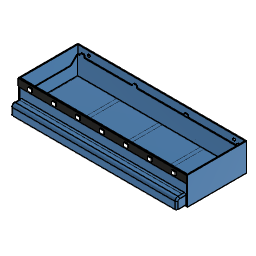
Large_Drawer_Assembly (Autodesk Fusion 360 design; units mm, degrees)
Autodesk Fusion 360 part; units mm, degrees
sketch "Bottom" plane through (0, 0, 0) normal (0, 0, 1) x (1, 0, 0) in component "Large_Holder_PRINT v2"
  line L0 (0, 0) -> (232.6, 0)
  line L1 (232.6, 0) -> (232.6, 81.6)
  line L2 (232.6, 81.6) -> (0, 81.6)
  line L3 (0, 81.6) -> (0, 0)
  line L4 (1.2, 80.4) -> (231.4, 80.4)
  line L5 (231.4, 80.4) -> (231.4, 1.2)
  line L6 (231.4, 1.2) -> (1.2, 1.2)
  line L7 (1.2, 1.2) -> (1.2, 80.4)
  line L8 (3.2, 3.2) -> (3.2, 78.4)
  line L9 (33.4, 80.4) -> (34.2, 80.4)
  line L10 (34.2, 1.2) -> (33.4, 1.2)
  line L11 (66.4, 80.4) -> (67.2, 80.4)
  line L12 (67.2, 1.2) -> (66.4, 1.2)
  line L13 (99.4, 80.4) -> (100.2, 80.4)
  line L14 (100.2, 1.2032) -> (99.4, 1.2032)
  line L15 (132.4, 80.4) -> (133.2, 80.4)
  line L16 (133.2, 1.2) -> (132.4, 1.2)
  line L17 (165.4, 80.4) -> (166.2, 80.4)
  line L18 (166.2, 1.2) -> (165.4, 1.2)
  line L19 (198.4, 80.4) -> (199.2, 80.4)
  line L20 (199.2, 1.2) -> (198.4, 1.2)
  line L21 (229.4, 78.4) -> (229.4, 3.2)
  line L22 (231.4, 80.4) -> (232.2, 80.4)
  line L23 (232.2, 1.2) -> (231.4, 1.2)
  line L24 (3.2, 78.4) -> (113.9, 78.4)
  line L25 (113.9, 3.2) -> (3.2, 3.2)
  line L26 (229.4, 78.4) -> (118.7, 78.4)
  line L27 (229.4, 3.2) -> (113.8, 3.2)
  line L28 (118.7, 78.4) -> (113.9, 78.4)
  line L29 (113.9, 3.2) -> (113.8, 3.2)
  line L30 (56, 80.4) -> (56, 1.2)
  line L31 (61, 80.4) -> (61, 1.2)
  line L32 (113.8, 80.4) -> (113.8, 1.2)
  line L33 (118.8, 1.2) -> (118.8, 80.4)
  line L34 (171.6, 3.2) -> (171.6, 80.4)
  line L35 (176.6, 80.4) -> (176.6, 1.2)
  line L36 (171.6, 3.2) -> (171.6, 1.2)
  dimension "d1_1" = 1.2
  dimension "d2_1" = 1.2
  dimension "d3_1" = 1.2
  dimension "d4_1" = 1.2
  dimension "d5_1" = 2
  dimension "d8_1" = 81.6
  dimension "d52" = 2
  dimension "d191" = 2
  dimension "d192" = 2
  dimension "d194" = 2
  dimension "d195" = 2
  dimension "d306" = 5
  dimension "d307" = 5
  dimension "d308" = 52.8
  dimension "d311" = 52.8
  dimension "d312" = 52.8
  dimension "d313" = 5
  dimension "d318" = 52.8
  constraint horizontal L0
  constraint vertical L1
  constraint horizontal L2
  constraint vertical L3
  constraint coincident L0.start L3.end
  constraint horizontal L4
  constraint vertical L5
  constraint horizontal L6
  constraint vertical L7
  constraint vertical L8
  constraint horizontal L9
  constraint coincident L6 L10.start
  constraint coincident L4 L9.start
  constraint horizontal L11
  constraint horizontal L12
  constraint coincident L4 L11.start
  constraint horizontal L13
  constraint horizontal L14
  constraint coincident L4 L13.start
  constraint horizontal L15
  constraint horizontal L16
  constraint coincident L4 L15.start
  constraint horizontal L17
  constraint horizontal L18
  constraint coincident L4 L17.start
  constraint horizontal L19
  constraint horizontal L20
  constraint coincident L4 L19.start
  constraint vertical L21
  constraint horizontal L22
  constraint horizontal L23
  constraint coincident L4 L5.start
  constraint perpendicular L8 L25
  constraint coincident L4 L30.start
  constraint coincident L6 L30.end
  constraint perpendicular L6 L30
  constraint coincident L4 L31.start
  constraint coincident L6 L31.end
  constraint perpendicular L0 L31
  constraint coincident L4 L32.start
  constraint coincident L6 L32.end
  constraint perpendicular L6 L32
  constraint coincident L6 L33.start
  constraint perpendicular L4 L33
  constraint coincident L4 L33.end
  constraint midpoint L27 L34.start
  constraint coincident L4 L34.end
  constraint perpendicular L4 L34
  constraint coincident L4 L35.start
  constraint coincident L6 L35.end
  constraint perpendicular L6 L35
  constraint coincident L6 L36.end
  constraint perpendicular L6 L36
  measures "d1_1" distance of L3 L7
  measures "d2_1" distance of L2 L4
  measures "d3_1" distance of L0 L6
  measures "d4_1" distance of L1 L5
  measures "d5_1" distance of L7 L8
  measures "d8_1" distance of L0.start L2.end
  measures "d52" distance of L5 L21
  measures "d191" distance of L4 L24
  measures "d192" distance of L6 L25
  measures "d194" distance of L6 L27
  measures "d195" distance of L4 L26
  measures "d306" distance of L30 L31
  measures "d307" distance of L32 L33
  measures "d308" distance of L8 L30
  measures "d311" distance of L31 L32
  measures "d312" distance of L33 L34
  measures "d313" distance of L34 L35
  measures "d318" distance of L21 L35
extrude "Extrude2" add sketch "Bottom" along normal blind 38.2 makes body 1 in component "Large_Holder_PRINT v2"
sketch "Front" plane through (0, 0, 0) normal (0, -1, 0) x (1, 0, 0) in component "Large_Holder_PRINT v2"
  line L0 (0, 0) -> (232.6, 0)
  line L1 (232.6, 0) -> (232.6, 38.2)
  line L2 (232.6, 38.2) -> (0, 38.2)
  line L3 (0, 38.2) -> (0, 0)
  line L4 (1.2, 28.2) -> (33.4, 28.2)
  line L5 (33.4, 1.2) -> (1.2, 1.2)
  line L6 (1.2, 1.2) -> (1.2, 28.2)
  line L7 (1.2, 0) -> (1.2, 38.2)
  line L8 (231.4, 28.2) -> (231.4, 1.2)
  line L9 (33.4, 28.2) -> (231.4, 28.2)
  line L10 (231.4, 1.2) -> (33.4, 1.2)
  dimension "d80" = 27
  dimension "d83" = 10
  dimension "d91" = 27
  dimension "d319" = 1.2
  constraint horizontal L4
  constraint horizontal L5
  constraint vertical L6
  constraint collinear L6 L7
  constraint vertical L8
  constraint perpendicular L8 L9
  measures "d80" distance of L4.start L5.end
  measures "d83" distance of L2 L4
  measures "d91" distance of L8.start L8.end
  measures "d319" distance of L1 L8
sketch "Back" plane through (0, 80.4, 0) normal (0, -1, 0) x (1, 0, 0) in component "Large_Holder_PRINT v2"
  line L0 (231.4, 0) -> (231.4, 38.2)
  line L1 (231.4, 38.2) -> (1.2, 38.2)
  line L2 (1.2, 38.2) -> (1.2, 0)
  line L3 (3.2, 6.7355) -> (6.7355, 3.2)
  line L4 (6.7355, 3.2) -> (27.8645, 3.2)
  line L5 (6.7355, 26.2711) -> (3.2, 22.7355)
  line L6 (3.2, 22.7355) -> (3.2, 6.7355)
  line L7 (27.8645, 26.271) -> (27.8645, 26.2711)
  line L8 (31.4, 6.7355) -> (31.4, 22.7355)
  line L9 (31.4, 22.7355) -> (27.8645, 26.2711)
  line L10 (1.2, 0) -> (231.4, 0)
  line L11 (27.8645, 3.2) -> (31.4, 6.7355)
  line L12 (27.8645, 26.271) -> (6.7355, 26.2711)
  line L13 (60.8645, 26.2728) -> (39.7355, 26.2729)
  line L14 (39.7355, 26.2729) -> (36.2, 22.7374)
  line L15 (36.2, 22.7374) -> (36.2, 6.7374)
  line L16 (36.2, 6.7374) -> (39.7355, 3.2019)
  line L17 (39.7355, 3.2019) -> (60.8645, 3.2019)
  line L18 (60.8645, 3.2019) -> (64.4, 6.7374)
  line L19 (64.4, 6.7374) -> (64.4, 22.7374)
  line L20 (93.8645, 26.271) -> (72.7355, 26.2711)
  line L21 (72.7355, 26.2711) -> (69.2, 22.7355)
  line L22 (69.2, 22.7355) -> (69.2, 6.7355)
  line L23 (69.2, 6.7355) -> (72.7355, 3.2)
  line L24 (72.7355, 3.2) -> (93.8645, 3.2)
  line L25 (93.8645, 3.2) -> (97.4, 6.7355)
  line L26 (97.4, 6.7355) -> (97.4, 22.7355)
  line L27 (126.8645, 26.271) -> (105.7355, 26.2711)
  line L28 (105.7355, 26.2711) -> (102.2, 22.7355)
  line L29 (102.2, 22.7355) -> (102.2, 6.7355)
  line L30 (102.2, 6.7355) -> (105.7355, 3.2)
  line L31 (105.7355, 3.2) -> (126.8645, 3.2)
  line L32 (126.8645, 3.2) -> (130.4, 6.7355)
  line L33 (130.4, 6.7355) -> (130.4, 22.7355)
  line L34 (159.8645, 26.271) -> (138.7355, 26.2711)
  line L35 (138.7355, 26.2711) -> (135.2, 22.7355)
  line L36 (135.2, 22.7355) -> (135.2, 6.7355)
  line L37 (135.2, 6.7355) -> (138.7355, 3.2)
  line L38 (138.7355, 3.2) -> (159.8645, 3.2)
  line L39 (159.8645, 3.2) -> (163.4, 6.7355)
  line L40 (163.4, 6.7355) -> (163.4, 22.7355)
  line L41 (192.8645, 26.271) -> (171.7355, 26.2711)
  line L42 (171.7355, 26.2711) -> (168.2, 22.7355)
  line L43 (168.2, 22.7355) -> (168.2, 6.7355)
  line L44 (168.2, 6.7355) -> (171.7355, 3.2)
  line L45 (171.7355, 3.2) -> (192.8645, 3.2)
  line L46 (192.8645, 3.2) -> (196.4, 6.7355)
  line L47 (196.4, 6.7355) -> (196.4, 22.7355)
  line L48 (225.8645, 26.271) -> (204.7355, 26.2711)
  line L49 (204.7355, 26.2711) -> (201.2, 22.7355)
  line L50 (201.2, 22.7355) -> (201.2, 6.7355)
  line L51 (201.2, 6.7355) -> (204.7355, 3.2)
  line L52 (204.7355, 3.2) -> (225.8645, 3.2)
  line L53 (225.8645, 3.2) -> (229.4, 6.7355)
  line L54 (229.4, 6.7355) -> (229.4, 22.7355)
  line L55 (232.6, 0) -> (232.6, 38.2)
  line L56 (0, 0) -> (0, 38.2)
  line L57 (60.8645, 26.2728) -> (64.4, 22.7374)
  line L58 (97.4, 22.7355) -> (93.8645, 26.271)
  line L59 (130.4, 22.7355) -> (126.8645, 26.271)
  line L60 (163.4, 22.7355) -> (159.8645, 26.271)
  line L61 (196.4, 22.7355) -> (192.8645, 26.271)
  line L62 (229.4, 22.7355) -> (225.8645, 26.271)
  dimension "d97" = 5
  dimension "d99" = 5
  dimension "d179" = 5
  dimension "d201" = 28.2
  dimension "d202" = 5
  dimension "d206" = 3.2
  dimension "d208" = 135
  dimension "d209" = 135
  dimension "d210" = 135
  dimension "d212" = 16
  dimension "d213" = 21.1289
  dimension "d215" = 135
  dimension "d216" = 135
  dimension "d219" = 5
  dimension "d220" = 5
  dimension "d222" = 28.2
  dimension "d223" = 5
  dimension "d224" = 16
  dimension "d225" = 135
  dimension "d226" = 135
  dimension "d228" = 16
  dimension "d229" = 21.1289
  dimension "d230" = 135
  dimension "d232" = 5
  dimension "d233" = 5
  dimension "d235" = 28.2
  dimension "d236" = 5
  dimension "d238" = 135
  dimension "d239" = 135
  dimension "d241" = 16
  dimension "d242" = 21.1289
  dimension "d243" = 135
  dimension "d245" = 5
  dimension "d246" = 5
  dimension "d248" = 28.2
  dimension "d249" = 5
  dimension "d250" = 16
  dimension "d251" = 135
  dimension "d252" = 135
  dimension "d254" = 16
  dimension "d255" = 21.1289
  dimension "d256" = 135
  dimension "d258" = 5
  dimension "d259" = 5
  dimension "d261" = 28.2
  dimension "d262" = 5
  dimension "d263" = 16
  dimension "d264" = 135
  dimension "d265" = 135
  dimension "d267" = 16
  dimension "d268" = 21.1289
  dimension "d269" = 135
  dimension "d271" = 5
  dimension "d272" = 5
  dimension "d274" = 28.2
  dimension "d275" = 5
  dimension "d276" = 16
  dimension "d277" = 135
  dimension "d278" = 135
  dimension "d280" = 16
  dimension "d281" = 21.1289
  dimension "d282" = 135
  dimension "d284" = 5
  dimension "d285" = 5
  dimension "d287" = 28.2
  dimension "d288" = 5
  dimension "d289" = 16
  dimension "d290" = 135
  dimension "d291" = 135
  dimension "d293" = 16
  dimension "d294" = 21.1289
  dimension "d295" = 135
  dimension "d297" = 4.8
  dimension "d298" = 4.8
  dimension "d299" = 4.8
  dimension "d300" = 4.8
  dimension "d301" = 4.8
  dimension "d302" = 4.8
  dimension "d304" = 3.2
  dimension "d305" = 4.9999
  dimension "d320" = 3.2019
  dimension "d321" = 3.2
  dimension "d323" = 3.2
  constraint parallel L2 L6
  constraint vertical L8
  constraint vertical L19
  constraint vertical L26
  constraint vertical L33
  constraint vertical L40
  constraint vertical L47
  constraint vertical L54
  measures "d97" distance of L5.start L5.end
  measures "d99" distance of L3.start L3.end
  measures "d179" distance of L8.end L7.end
  measures "d201" distance of L6 L8
  measures "d202" distance of L4.end L8.start
  measures "d206" distance of L4 L10
  measures "d208" angle of L3 L4
  measures "d209" angle of L8 L11
  measures "d210" angle of L8 L9
  measures "d212" distance of L3.start L5.end
  measures "d213" horizontal distance of L7.start L5.start
  measures "d215" angle of L5 L12
  measures "d216" angle of L9 L12
  measures "d219" distance of L14.end L13.end
  measures "d220" distance of L15.end L16.end
  measures "d222" distance of L15 L19
  measures "d223" distance of L18.end L17.end
  measures "d224" distance of L18.end L19.end
  measures "d225" angle of L16 L17
  measures "d226" angle of L18 L19
  measures "d228" distance of L15.end L14.end
  measures "d229" horizontal distance of L13.start L13.end
  measures "d230" angle of L13 L14
  measures "d232" distance of L21.end L20.end
  measures "d233" distance of L22.end L23.end
  measures "d235" distance of L22 L26
  measures "d236" distance of L25.end L24.end
  measures "d238" angle of L23 L24
  measures "d239" angle of L25 L26
  measures "d241" distance of L22.end L21.end
  measures "d242" horizontal distance of L20.start L20.end
  measures "d243" angle of L20 L21
  measures "d245" distance of L28.end L27.end
  measures "d246" distance of L29.end L30.end
  measures "d248" distance of L29 L33
  measures "d249" distance of L32.end L31.end
  measures "d250" distance of L32.end L33.end
  measures "d251" angle of L30 L31
  measures "d252" angle of L32 L33
  measures "d254" distance of L29.end L28.end
  measures "d255" horizontal distance of L27.start L27.end
  measures "d256" angle of L27 L28
  measures "d258" distance of L35.end L34.end
  measures "d259" distance of L36.end L37.end
  measures "d261" distance of L36 L40
  measures "d262" distance of L39.end L38.end
  measures "d263" distance of L39.end L40.end
  measures "d264" angle of L37 L38
  measures "d265" angle of L39 L40
  measures "d267" distance of L36.end L35.end
  measures "d268" horizontal distance of L34.start L34.end
  measures "d269" angle of L34 L35
  measures "d271" distance of L42.end L41.end
  measures "d272" distance of L43.end L44.end
  measures "d274" distance of L43 L47
  measures "d275" distance of L46.end L45.end
  measures "d276" distance of L46.end L47.end
  measures "d277" angle of L44 L45
  measures "d278" angle of L46 L47
  measures "d280" distance of L43.end L42.end
  measures "d281" horizontal distance of L41.start L41.end
  measures "d282" angle of L41 L42
  measures "d284" distance of L49.end L48.end
  measures "d285" distance of L50.end L51.end
  measures "d287" distance of L50 L54
  measures "d288" distance of L53.end L52.end
  measures "d289" distance of L53.end L54.end
  measures "d290" angle of L51 L52
  measures "d291" angle of L53 L54
  measures "d293" distance of L50.end L49.end
  measures "d294" horizontal distance of L48.start L48.end
  measures "d295" angle of L48 L49
  measures "d297" distance of L8 L15
  measures "d298" distance of L19 L22
  measures "d299" distance of L26 L29
  measures "d300" distance of L33 L36
  measures "d301" distance of L40 L43
  measures "d302" distance of L47 L50
  measures "d304" distance of L6 L56
  measures "d305" distance of L40.end L34.start
  measures "d320" distance of L10 L17
  measures "d321" distance of L10 L24
  measures "d323" distance of L10 L31
sketch "Mounting" plane through (0, 80.4, 0) normal (0, -1, 0) x (1, 0, 0) in component "Large_Holder_PRINT v2"
  line L0 (231.4, 0) -> (231.4, 38.2)
  line L1 (231.4, 38.2) -> (1.2, 38.2)
  line L2 (1.2, 38.2) -> (1.2, 0)
  circle A0 centre (216.3, 32.2) radius 2
  circle A1 centre (16.3, 32.2) radius 2
  line L3 (1.2, 0) -> (231.4, 0)
  dimension "d165" = 4
  dimension "d166" = 4
  dimension "d167" = 15.1
  dimension "d168" = 6
  dimension "d169" = 15.1
  dimension "d170" = 6
  measures "d165" diameter of A0
  measures "d166" diameter of A1
  measures "d167" distance of L2 A1.centre
  measures "d168" distance of L1 A1.centre
  measures "d169" distance of L0 A0.centre
  measures "d170" distance of L1 A0.centre
extrude "Extrude9" cut sketch "Front" against normal up to surface (1.2 mm away) contours L4 L5 L6 L7 L8 L9 L10 bodies 1 in component "Large_Holder_PRINT v2"
extrude "Extrude10" cut sketch "Back" against normal blind 1.2 contours L3 L4 L5 L6 L8 L9 L11 L12 | L13 L14 L15 L16 L17 L18 L19 L57 | L20 L21 L22 L23 L24 L25 L26 L58 | L27 L28 L29 L30 L31 L32 L33 L59 | L34 L35 L36 L37 L38 L39 L40 L60 | L41 L42 L43 L44 L45 L46 L47 L61 | L48 L49 L50 L51 L52 L53 L54 L62 bodies 1 in component "Large_Holder_PRINT v2"
extrude "Extrude11" cut sketch "Mounting" against normal blind 1.2 contours A0 | A1 bodies 1 in component "Large_Holder_PRINT v2"
extrude "Extrude12" add sketch "Bottom" along normal up to surface (1.2 mm away) contours L4 L6 L7 L8 L9 L10 L24 L25 L30 | L4 L24 L30 L31 | L4 L11 L13 L24 L31 L32 | L6 L25 L30 L31 | L6 L12 L25 L31 L32 | L4 L24 L26 L28 L32 L33 | L6 L25 L27 L29 L32 L33 | L4 L15 L17 L26 L33 L34 | L6 L16 L18 L27 L33 L36 | L4 L26 L34 L35 | L6 L27 L35 L36 | L4 L5 L6 L19 L20 L21 L26 L27 L35 bodies 1 in component "Large_Holder_PRINT v2"
extrude "Extrude13" add sketch "Bottom" along normal up to surface (1.2 mm away) contours L4 L6 L7 L8 L9 L10 L24 L25 L30 | L4 L24 L30 L31 | L4 L11 L13 L24 L31 L32 | L6 L25 L30 L31 | L6 L12 L25 L31 L32 | L4 L24 L26 L28 L32 L33 | L6 L25 L27 L29 L32 L33 | L4 L15 L17 L26 L33 L34 | L6 L16 L18 L27 L33 L36 | L4 L26 L34 L35 | L6 L27 L35 L36 | L4 L5 L6 L19 L20 L21 L26 L27 L35 bodies 1 in component "Large_Holder_PRINT v2"
extrude "Extrude15" add sketch "Bottom" along normal blind 1.2 contours L24 L25 L30 L31 | L24 L25 L26 L27 L28 L29 L32 L33 | L26 L27 L34 L35 bodies 1 in component "Large_Holder_PRINT v2"
sketch "Sketch1" plane through (0, 0, 0) normal (0, 0, 1) x (1, 0, 0) in component "Large_Drawer_PRINT v1"
  line L0 (0, 0) -> (229.4, 0)
  line L1 (229.4, 0) -> (229.4, 80)
  line L2 (229.4, 80) -> (0, 80)
  line L3 (0, 80) -> (0, 0)
  dimension "d1_2" = 229.4
  dimension "d2_2" = 80
  constraint horizontal L0
  constraint vertical L1
  constraint horizontal L2
  constraint vertical L3
  constraint coincident L0.start L3.end
  measures "d1_2" distance of L0.start L0.end
  measures "d2_2" distance of L0.end L1.end
extrude "Extrude1" add sketch "Sketch1" along normal blind 26.2 separate body makes body 2 in component "Large_Drawer_PRINT v1"
shell "Shell1" thickness 0.8 removed faces 1 at (76.4667, 26.6667, 26.2) on bodies 2 in component "Large_Drawer_PRINT v1"
ref_plane "WorkPlane1" through (211, 40, 13.1) normal (1, 0, 0) x (0, 1, 0) in component "Large_Drawer_PRINT v1"
sketch "Sketch3" plane through (0, 80, 0) normal (0, 1, 0) x (-1, 0, 0) in component "Large_Drawer_PRINT v1"
  line L0 (-229.4, 0) -> (0, 0)
  line L1 (0, 0) -> (0, 26.2)
  line L2 (0, 26.2) -> (-229.4, 26.2)
  line L3 (-229.4, 26.2) -> (-229.4, 0)
  line L4 (-114.7, 26.2) -> (-114.7, 0) construction
  line L5 (-225.15, 27.45) -> (-225.15, 28.45)
  line L6 (-223.9, 29.7) -> (-220.9, 29.7)
  line L7 (-219.65, 28.45) -> (-219.65, 27.45)
  line L8 (-226.4, 26.2) -> (-218.4, 26.2)
  arc A0 (-226.4, 26.2) -> (-225.15, 27.45) centre (-226.4, 27.45) ccw
  arc A1 (-223.9, 29.7) -> (-225.15, 28.45) centre (-223.9, 28.45) ccw
  arc A2 (-219.65, 28.45) -> (-220.9, 29.7) centre (-220.9, 28.45) ccw
  arc A3 (-219.65, 27.45) -> (-218.4, 26.2) centre (-218.4, 27.45) ccw
  arc A4 (-4.25, 28.45) -> (-5.5, 29.7) centre (-5.5, 28.45) ccw
  line L9 (-5.5, 29.7) -> (-8.5, 29.7)
  arc A5 (-11, 26.2) -> (-9.75, 27.45) centre (-11, 27.45) ccw
  arc A6 (-4.25, 27.45) -> (-3, 26.2) centre (-3, 27.45) ccw
  line L10 (-4.25, 27.45) -> (-4.25, 28.45)
  line L11 (-3, 26.2) -> (-11, 26.2)
  arc A7 (-8.5, 29.7) -> (-9.75, 28.45) centre (-8.5, 28.45) ccw
  line L12 (-9.75, 28.45) -> (-9.75, 27.45)
  line L13 (-151.4, 29.7129) -> (-148.4, 29.7129)
  arc A8 (-151.4, 29.7129) -> (-152.65, 28.4629) centre (-151.4, 28.4629) ccw
  line L14 (-152.65, 27.4629) -> (-152.65, 28.4629)
  arc A9 (-153.9, 26.2129) -> (-152.65, 27.4629) centre (-153.9, 27.4629) ccw
  arc A10 (-147.15, 27.4629) -> (-145.9, 26.2129) centre (-145.9, 27.4629) ccw
  line L15 (-153.9, 26.2129) -> (-145.9, 26.2129)
  line L16 (-147.15, 28.4629) -> (-147.15, 27.4629)
  arc A11 (-147.15, 28.4629) -> (-148.4, 29.7129) centre (-148.4, 28.4629) ccw
  line L17 (-81, 29.7) -> (-78, 29.7)
  arc A12 (-81, 29.7) -> (-82.25, 28.45) centre (-81, 28.45) ccw
  line L18 (-82.25, 27.45) -> (-82.25, 28.45)
  arc A13 (-83.5, 26.2) -> (-82.25, 27.45) centre (-83.5, 27.45) ccw
  arc A14 (-76.75, 28.45) -> (-78, 29.7) centre (-78, 28.45) ccw
  line L19 (-76.75, 28.45) -> (-76.75, 27.45)
  arc A15 (-76.75, 27.45) -> (-75.5, 26.2) centre (-75.5, 27.45) ccw
  point P0 (-222.4, 29.7)
  point P1 (-7, 29.7)
  dimension "d18_1" = 7
  dimension "d19_1" = 3.5
  dimension "d20_1" = 5.5
  dimension "d21_1" = 1.25
  dimension "d62" = 3.5
  dimension "d63" = 5.5
  dimension "d64" = 1.25
  dimension "d65" = 114.3
  dimension "d66" = 67
  dimension "d75" = 5.5
  dimension "d76" = 1.25
  dimension "d77" = 3.5
  dimension "d78" = 67
  dimension "d79" = 54.15
  constraint midpoint L2 L4.start
  constraint perpendicular L2 L4
  constraint coincident L0 L4.end
  constraint horizontal L6
  constraint tangent L6 A1
  constraint tangent L5 A1
  constraint tangent L5 A0
  constraint tangent L6 A2
  constraint tangent L7 A2
  constraint tangent L7 A3
  constraint tangent L8 A3
  constraint tangent L8 A0
  constraint equal A0 A1
  constraint equal A1 A2
  constraint equal A2 A3
  constraint collinear L2 L8
  constraint vertical L7
  constraint vertical L5
  constraint midpoint L6 P0
  constraint symmetric L4 L5.start A6.start
  constraint symmetric L4 L5.end A4.start
  constraint symmetric L4 L6.start A4.end
  constraint symmetric L4 L6.end L9.end
  constraint symmetric L4 L7.start A7.end
  constraint symmetric L4 L7.end A5.end
  constraint symmetric L4 L8.start A6.end
  constraint symmetric L4 L8.end A5.start
  constraint symmetric L4 P0 P1
  constraint symmetric L4 A0 A6
  constraint symmetric L4 A1 A4
  constraint symmetric L4 A2 A7
  constraint symmetric L4 A3 A5
  constraint horizontal L13
  constraint tangent L13 A8
  constraint tangent A8 L14
  constraint tangent L14 A9
  constraint tangent L13 A11
  constraint tangent L16 A11
  constraint tangent A10 L16
  constraint tangent A10 L15
  constraint tangent A9 L15
  constraint equal A8 A9
  constraint equal A8 A11
  constraint equal A10 A11
  constraint vertical L16
  constraint vertical L14
  constraint horizontal L17
  constraint tangent L17 A12
  constraint tangent A12 L18
  constraint tangent L18 A13
  constraint tangent L17 A14
  constraint tangent A14 L19
  constraint tangent L19 A15
  constraint equal A12 A13
  constraint equal A12 A14
  constraint equal A14 A15
  constraint vertical L19
  constraint vertical L18
  measures "d18_1" distance of L3 P0
  measures "d19_1" distance of L6 L8
  measures "d20_1" distance of L5 L7
  measures "d21_1" radius of A0
  measures "d62" distance of L13 L15
  measures "d63" distance of L14 L16
  measures "d64" radius of A9
  measures "d66" distance of L7 L14
  measures "d75" distance of L18 L19
  measures "d76" radius of A13
  measures "d77" distance of L2 L17
  measures "d78" distance of L12 L19
extrude "Extrude3" add sketch "Sketch3" against normal blind 0.8 contours L2 L5 L6 L7 L8 A0 A1 A2 A3 | L2 A4 L9 A5 A6 L10 L11 A7 L12 | L2 L17 A12 L18 A13 A14 L19 A15 | L13 A8 L14 A9 A10 L15 L16 A11 bodies 2 makes body 3 at (150.4, 80, 28.2129) in component "Large_Drawer_PRINT v1"
sketch "Sketch4" plane through (229.4, 0, 0) normal (1, 0, 0) x (0, 1, 0) in component "Large_Drawer_PRINT v1"
  line L0 (0, 0) -> (80, 0)
  line L1 (80, 0) -> (80, 26.2)
  line L2 (80, 26.2) -> (0, 26.2)
  line L3 (0, 26.2) -> (0, 0)
  line L4 (0.9071, 26.2) -> (10.1071, 17)
  line L5 (0.9071, 26.2) -> (7.8528, 26.2) construction
  line L6 (10.1071, 17) -> (69.7311, 17)
  line L7 (69.7311, 17) -> (78.9311, 26.2)
  line L8 (78.9311, 26.2) -> (0.9071, 26.2)
  dimension "d24_1" = 45
  dimension "d25_1" = 135
  dimension "d26_1" = 17
  constraint horizontal L5
  constraint coincident L2 L4.start
  constraint horizontal L6
  constraint coincident L2 L7.end
  measures "d24_1" angle of L4 L5
  measures "d25_1" angle of L6 L7
  measures "d26_1" distance of L0 L6
extrude "Extrude4" cut sketch "Sketch4" against normal up to surface (229.4 mm away) contours L2 L4 L6 L7 L8 bodies 2 in component "Large_Drawer_PRINT v1"
extrude "Extrude5" add 1 faces at (104.3, 79.2, 9.2667) along direction (0, -1, 0) blind 0.4 on bodies 2 bodies 2 in component "Large_Drawer_PRINT v1"
sketch "Sketch5" plane through (0, 0, 0) normal (0, -1, 0) x (1, 0, 0) in component "Large_Drawer_PRINT v1"
  line L0 (0, 0) -> (229.4, 0)
  line L1 (229.4, 0) -> (229.4, 26.2)
  line L2 (229.4, 26.2) -> (0, 26.2)
  line L3 (0, 26.2) -> (0, 0)
  line L4 (0.5, 13.8) -> (228.9, 13.8)
  line L5 (228.9, 13.8) -> (228.9, 13)
  line L6 (228.9, 13) -> (0.5, 13)
  line L7 (0.5, 13) -> (0.5, 13.8)
  dimension "d31_1" = 0.5
  dimension "d32_1" = 0.5
  dimension "d33_1" = 0.8
  dimension "d34_1" = 13
  constraint horizontal L4
  constraint vertical L5
  constraint horizontal L6
  constraint vertical L7
  measures "d31_1" distance of L3 L7
  measures "d32_1" distance of L1 L5
  measures "d33_1" distance of L4 L6
  measures "d34_1" distance of L0 L6
extrude "Extrude6" add sketch "Sketch5" along normal blind 13 contours L4 L5 L6 L7 bodies 2 in component "Large_Drawer_PRINT v1"
sketch "Sketch6" plane through (0, 0, 13) normal (0, 0, -1) x (1, 0, 0) in component "Large_Drawer_PRINT v1"
  line L0 (0.5, 0) -> (228.9, 0)
  line L1 (228.9, 0) -> (228.9, 13)
  line L2 (228.9, 13) -> (0.5, 13)
  line L3 (0.5, 13) -> (0.5, 0)
  line L4 (0.5, 13) -> (31.3, 13)
  line L5 (31.3, 12.2) -> (0.5, 12.2)
  line L6 (0.5, 12.2) -> (0.5, 13)
  line L7 (31.3, 13) -> (228.9, 13)
  line L8 (31.3, 12.2) -> (228.9, 12.2)
  line L9 (228.9, 12.2) -> (228.9, 13)
  dimension "d37" = 0.8
  constraint horizontal L4
  constraint horizontal L5
  constraint vertical L6
  constraint coincident L2.end L3.start
  constraint coincident L1.end L2.start
  constraint coincident L1 L8.end
  constraint perpendicular L1 L8
  measures "d37" distance of L2.end L5.end
extrude "Extrude7" add sketch "Sketch6" along normal blind 13 contours L1 L2 L3 L4 L5 L6 L7 L8 L9 bodies 2 in component "Large_Drawer_PRINT v1"
sketch "Sketch8" plane through (0, 0, 13) normal (0, 0, -1) x (1, 0, 0) in component "Large_Drawer_PRINT v1"
  line L0 (228.9, 12.2) -> (0.5, 12.2)
  line L1 (0.5, 12.2) -> (0.5, 0)
  line L2 (0.5, 0) -> (228.9, 0)
  line L3 (228.9, 0) -> (228.9, 12.2)
  line L4 (1.3, 0) -> (0.5, 0)
  line L5 (0.5, 0) -> (0.5, 12.2)
  line L6 (0.5, 12.2) -> (1.3, 12.2)
  line L7 (1.3, 12.2) -> (1.3, 0)
  line L8 (228.9, 0) -> (228.1, 0)
  line L9 (228.1, 0) -> (228.1, 12.2)
  line L10 (228.1, 12.2) -> (228.9, 12.2)
  line L11 (228.9, 12.2) -> (228.9, 0)
  dimension "d45" = 0.8
  dimension "d46" = 0.8
  constraint horizontal L4
  constraint vertical L5
  constraint horizontal L6
  constraint vertical L7
  constraint coincident L0.end L1.start
  constraint coincident L2 L4.start
  constraint horizontal L8
  constraint vertical L9
  constraint horizontal L10
  constraint vertical L11
  constraint coincident L0 L9.end
  constraint coincident L2.end L3.start
  measures "d45" distance of L9.end L0.start
  measures "d46" distance of L0.end L6.end
extrude "Extrude9'" add sketch "Sketch8" along normal blind 13 contours L0 L2 L3 L8 L9 L10 L11 | L0 L1 L2 L4 L5 L6 L7 bodies 2 in component "Large_Drawer_PRINT v1"
fillet "Fillet2" radius 4 2 edges at (114.7, -12.2, 13) (114.7, -13, 13.8) on bodies 2 in component "Large_Drawer_PRINT v1"
chamfer "Chamfer1" distance 3 angle 45 1 edges at (114.7, 0, 13) on bodies 2 in component "Large_Drawer_PRINT v1"
fillet "Fillet4" radius 2 6 edges at (1.3, -12.2, 4.5) (1.3, -11.0284, 11.8284) (1.3, -5.6, 13) (0.5, -4.5, 13.8) (0.5, -11.8284, 12.6284) (0.5, -13, 4.9) on bodies 2 in component "Large_Drawer_PRINT v1"
fillet "Fillet5" radius 2 3 edges at (228.1, -5.6, 13) (228.1, -11.0284, 11.8284) (228.1, -12.2, 4.5) on bodies 2 in component "Large_Drawer_PRINT v1"
fillet "Fillet6" radius 2 3 edges at (228.9, -4.5, 13.8) (228.9, -11.8284, 12.6284) (228.9, -13, 4.9) on bodies 2 in component "Large_Drawer_PRINT v1"
sketch "Sketch1 (2)" plane through (0, 0, 0) normal (0, -1, 0) x (1, 0, 0)
  line L0 (231.4, 1.2) -> (1.2, 1.2)
  line L1 (1.2, 1.2) -> (1.2, 28.2)
  line L2 (1.2, 28.2) -> (231.4, 28.2)
  line L3 (231.4, 28.2) -> (231.4, 1.2)
  line L4 (0, 0) -> (232.6, 0)
  line L5 (232.6, 0) -> (232.6, 38.2)
  line L6 (232.6, 38.2) -> (0, 38.2)
  line L7 (0, 38.2) -> (0, 0)
  line L8 (0, 38.2) -> (232.6, 38.2)
  line L9 (232.6, 38.2) -> (232.6, 28.2)
  line L10 (232.6, 28.2) -> (0, 28.2)
  line L11 (0, 28.2) -> (0, 38.2)
  dimension "d1" = 10
  constraint horizontal L8
  constraint vertical L9
  constraint horizontal L10
  constraint vertical L11
  constraint coincident L5 L9.end
  constraint coincident L6.end L7.start
  measures "d1" distance of L5.end L9.end
extrude "Extrude1'" add sketch "Sketch1 (2)" along normal blind 1 separate body contours L2 L5 L6 L7 L8 L9 L10 L11 makes body 4
sketch "Sketch2" plane through (0, -1, 0) normal (0, -1, 0) x (1, 0, 0)
  line L0 (0, 28.2) -> (232.6, 28.2)
  line L1 (232.6, 28.2) -> (232.6, 38.2)
  line L2 (232.6, 38.2) -> (0, 38.2)
  line L3 (0, 38.2) -> (0, 28.2)
  line L4 (15, 35.7) -> (20, 35.7)
  line L5 (20, 35.7) -> (20, 30.7)
  line L6 (20, 30.7) -> (15, 30.7)
  line L7 (15, 30.7) -> (15, 35.7)
  line L8 (48, 35.7) -> (53, 35.7)
  line L9 (48, 30.7) -> (48, 35.7)
  line L10 (53, 30.7) -> (48, 30.7)
  line L11 (53, 35.7) -> (53, 30.7)
  line L12 (48, 35.7) -> (53, 35.7)
  line L13 (48, 30.7) -> (48, 35.7)
  line L14 (53, 30.7) -> (48, 30.7)
  line L15 (53, 35.7) -> (53, 30.7)
  line L16 (81, 35.7) -> (86, 35.7)
  line L17 (81, 30.7) -> (81, 35.7)
  line L18 (86, 30.7) -> (81, 30.7)
  line L19 (86, 35.7) -> (86, 30.7)
  line L20 (114, 35.7) -> (119, 35.7)
  line L21 (114, 30.7) -> (114, 35.7)
  line L22 (119, 30.7) -> (114, 30.7)
  line L23 (119, 35.7) -> (119, 30.7)
  line L24 (147, 35.7) -> (152, 35.7)
  line L25 (152, 35.7) -> (152, 30.7)
  line L26 (152, 30.7) -> (147, 30.7)
  line L27 (147, 30.7) -> (147, 35.7)
  line L28 (180, 35.7) -> (185, 35.7)
  line L29 (185, 35.7) -> (185, 30.7)
  line L30 (185, 30.7) -> (180, 30.7)
  line L31 (180, 30.7) -> (180, 35.7)
  line L32 (213, 35.7) -> (218, 35.7)
  line L33 (218, 35.7) -> (218, 30.7)
  line L34 (218, 30.7) -> (213, 30.7)
  line L35 (213, 30.7) -> (213, 35.7)
  dimension "d4" = 5
  dimension "d5" = 15
  dimension "d6" = 5
  dimension "d7" = 28
  dimension "d8" = 2.5
  dimension "d9" = 2.5
  dimension "d10" = 5
  dimension "d11" = 5
  dimension "d12" = 28
  dimension "d13" = 2.5
  dimension "d14" = 5
  dimension "d15" = 5
  dimension "d16" = 28
  dimension "d17" = 2.5
  dimension "d18" = 5
  dimension "d19" = 5
  dimension "d20" = 28
  dimension "d21" = 5
  dimension "d22" = 5
  dimension "d23" = 2.5
  dimension "d24" = 28
  dimension "d25" = 5
  dimension "d26" = 5
  dimension "d27" = 2.5
  dimension "d28" = 28
  dimension "d29" = 5
  dimension "d30" = 5
  dimension "d31" = 2.5
  dimension "d32" = 28
  constraint horizontal L4
  constraint vertical L5
  constraint horizontal L6
  constraint vertical L7
  constraint horizontal L8
  constraint vertical L11
  constraint horizontal L10
  constraint vertical L9
  constraint horizontal L12
  constraint vertical L15
  constraint horizontal L14
  constraint vertical L13
  constraint horizontal L16
  constraint vertical L19
  constraint horizontal L18
  constraint vertical L17
  constraint horizontal L20
  constraint vertical L23
  constraint horizontal L22
  constraint vertical L21
  constraint horizontal L24
  constraint vertical L25
  constraint horizontal L26
  constraint vertical L27
  constraint horizontal L28
  constraint vertical L29
  constraint horizontal L30
  constraint vertical L31
  constraint horizontal L32
  constraint vertical L33
  constraint horizontal L34
  constraint vertical L35
  measures "d4" distance of L4.start L4.end
  measures "d5" distance of L3 L7
  measures "d6" distance of L4.end L5.end
  measures "d7" distance of L5 L9
  measures "d8" distance of L2 L4
  measures "d9" distance of L2 L12
  measures "d10" distance of L8.start L9.start
  measures "d11" distance of L10.start L9.start
  measures "d12" distance of L5 L13
  measures "d13" distance of L2 L16
  measures "d14" distance of L16.start L16.end
  measures "d15" distance of L18.start L16.end
  measures "d16" distance of L15 L17
  measures "d17" distance of L2 L20
  measures "d18" distance of L20.start L21.start
  measures "d19" distance of L22.start L21.start
  measures "d20" distance of L19 L21
  measures "d21" distance of L24.start L24.end
  measures "d22" distance of L24.end L25.end
  measures "d23" distance of L2 L24
  measures "d24" distance of L23 L27
  measures "d25" distance of L28.start L28.end
  measures "d26" distance of L28.end L29.end
  measures "d27" distance of L2 L28
  measures "d28" distance of L25 L31
  measures "d29" distance of L32.start L32.end
  measures "d30" distance of L32.end L33.end
  measures "d31" distance of L2 L32
  measures "d32" distance of L29 L35
extrude "Extrude2'" add sketch "Sketch2" along normal blind 1.5 contours L4 L5 L6 L7 | L8 L9 L10 L11 L12 L13 L14 L15 | L16 L17 L18 L19 | L20 L21 L22 L23 | L24 L25 L26 L27 | L28 L29 L30 L31 | L32 L33 L34 L35 bodies 4
component "Large_Holder_PRINT v2" placed x (1, 0, 0) y (0, 1, 0) z (0, 0, 1) at (0, 0, 0)
component "Large_Drawer_PRINT v1" placed x (1, 0, 0) y (0, 1, 0) z (0, 0, 1) at (1.5, 0, 1.5)
equation "d1_2 = 230.2 mm - 0.8 mm"
